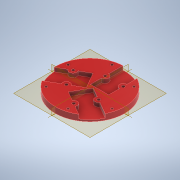
# Autodesk Inventor part: Base
Saved by Autodesk Inventor 2021 (Build 250183000, 183)
## iProperties
Created: 2026-04-21
Part Number: Base
Material: Generic
Document SubType Name: Modeling
Designer: Admin
Density: 1 g/cm^3
Appearance: Red
Author: Admin
Autodesk Inventor part; units mm, degrees
sketch "Sketch1" plane through (0, 0, 0) normal (0, 1, 0) x (-1, 0, 0)
  line L0 (-25, -40) -> (5, -40)
  line L1 (5, -40) -> (5, 0)
  line L2 (5, 0) -> (-25, 0)
  line L3 (-25, 0) -> (-25, -40)
  line L4 (-25, -40) -> (5, 0) construction
  line L5 (5, -40) -> (-25, 0) construction
  line L6 (-36.6337, 0) -> (44.8023, 0) projected
  line L7 (0, -54.5971) -> (0, 47.5827) projected
  point P0 (-10, -20)
  point P1 (0, -40)
  point P2 (0, 0)
  dimension "d15" = 30
  dimension "d16" = 40
  dimension "d17" = 10
  constraints: 12 end point, 2 midpoint, 2 parallel, 1 horizontal, 1 perpendicular, 1 point on line
  measures "d15" distance of L0.start L0.end
  measures "d16" distance of L2.end L0.start
  measures "d17" distance from line of L7 point (-10, -20)
extrude "Extrusion1" add sketch "Sketch1" along normal blind 8
pattern_circular "Circular Pattern2" count 3 over 360 about axis through (0, -10, 0) along (0, 1, 0) of "Extrusion1"
sketch "Sketch2" plane through (0, 8, 0) normal (0, 1, 0) x (1, 0, 0)
  line L0 (0, 54.5971) -> (0, -47.5827) projected
  line L1 (22.5, 40) -> (-2.5, 40)
  line L2 (-2.5, 40) -> (-2.5, 3)
  line L3 (-2.5, 3) -> (22.5, 3)
  line L4 (22.5, 3) -> (22.5, 40)
  line L5 (25, 40) -> (-5, 40) projected
  circle A0 centre (-2.5, 23) radius 5
  circle A1 centre (22.5, 23) radius 5
  point P0 (0, 0)
  point P1 (10, 40)
  point P2 (22.5, 18)
  point P3 (22.5, 28)
  point P4 (-2.5, 28)
  point P5 (-2.5, 18)
  dimension "d18" = 25
  dimension "d19" = 37
  dimension "d21" = 10
  dimension "d24" = 20
  dimension "d25" = 20
  constraints: 8 end point, 2 centre point, 2 midpoint, 2 parallel, 2 point on line, 1 equal radius, 1 horizontal, 1 perpendicular
  measures "d18" distance between parallel lines of L2 L4
  measures "d19" distance of L3.end L1.start
  measures "d21" diameter of A1
  measures "d24" distance from line of L3 A1.centre
  measures "d25" distance from line of L3 A0.centre
extrude "Extrusion2" cut sketch "Sketch2" against normal blind 5.5 contours L1 L4 A1 L3 L0 A0 | L0 A0 L2 L1 | L0 L3 L2 A0
pattern_circular "Circular Pattern3" count 3 over 360 about axis through (0, -10, 0) along (0, 1, 0) of "Extrusion2"
sketch "Sketch3" plane through (0, 0, 0) normal (0, 1, 0) x (-1, 0, 0)
  line L0 (12.5, -21.6506) -> (47.141, -1.6506) projected
  line L1 (32.141, 24.3301) -> (5, 8.6603) projected
  line L2 (12.5, 21.6506) -> (-22.141, 41.6506) projected
  line L3 (2.5, -40) -> (5, -40) projected
  line L4 (-35.891, 17.8349) -> (-37.141, 15.6699) projected
  line L5 (33.391, 22.1651) -> (32.141, 24.3301) projected
  line L6 (5, -8.6603) -> (12.5, -21.6506) projected
  line L7 (-23.391, 39.4856) -> (-12.9987, 33.4856) projected
  arc A0 (-12.9987, 33.4856) -> (-4.3385, 28.4856) centre (-8.6686, 30.9856) ccw projected
  line L8 (-4.3385, 28.4856) -> (8.6519, 20.9856) projected
  line L9 (8.6519, 20.9856) -> (-3.8481, -0.6651) projected
  line L10 (-3.8481, -0.6651) -> (-16.8385, 6.8349) projected
  arc A1 (-16.8385, 6.8349) -> (-25.4987, 11.8349) centre (-21.1686, 9.3349) ccw projected
  line L11 (-25.4987, 11.8349) -> (-35.891, 17.8349) projected
  line L12 (-35.891, 17.8349) -> (-37.141, 15.6699) projected
  line L13 (-37.141, 15.6699) -> (-10, 0) projected
  line L14 (-10, 0) -> (-25, 0) projected
  line L15 (-25, 0) -> (-25, -40) projected
  line L16 (-25, -40) -> (-22.5, -40) projected
  line L17 (-22.5, -40) -> (-22.5, -28) projected
  arc A2 (-22.5, -28) -> (-22.5, -18) centre (-22.5, -23) ccw projected
  line L18 (-22.5, -18) -> (-22.5, -3) projected
  line L19 (-22.5, -3) -> (2.5, -3) projected
  line L20 (2.5, -3) -> (2.5, -18) projected
  arc A3 (2.5, -18) -> (2.5, -28) centre (2.5, -23) ccw projected
  line L21 (2.5, -28) -> (2.5, -40) projected
  line L22 (2.5, -40) -> (5, -40) projected
  line L23 (5, -40) -> (5, -8.6603) projected
  line L24 (5, -8.6603) -> (12.5, -21.6506) projected
  line L25 (12.5, -21.6506) -> (47.141, -1.6506) projected
  line L26 (47.141, -1.6506) -> (45.891, 0.5144) projected
  line L27 (45.891, 0.5144) -> (35.4987, -5.4856) projected
  arc A4 (35.4987, -5.4856) -> (26.8385, -10.4856) centre (31.1686, -7.9856) ccw projected
  line L28 (26.8385, -10.4856) -> (13.8481, -17.9856) projected
  line L29 (13.8481, -17.9856) -> (1.3481, 3.6651) projected
  line L30 (1.3481, 3.6651) -> (14.3385, 11.1651) projected
  arc A5 (14.3385, 11.1651) -> (22.9987, 16.1651) centre (18.6686, 13.6651) ccw projected
  line L31 (22.9987, 16.1651) -> (33.391, 22.1651) projected
  line L32 (33.391, 22.1651) -> (32.141, 24.3301) projected
  line L33 (32.141, 24.3301) -> (5, 8.6603) projected
  line L34 (5, 8.6603) -> (12.5, 21.6506) projected
  line L35 (12.5, 21.6506) -> (-22.141, 41.6506) projected
  line L36 (-22.141, 41.6506) -> (-23.391, 39.4856) projected
  line L37 (-37.141, 15.6699) -> (-10, 0) projected
  line L38 (45.891, 0.5144) -> (48.967, 2.2903)
  line L39 (46.405, 29.6787) -> (33.391, 22.1651)
  line L40 (2.5, -40) -> (2.5, -52.4584)
  line L41 (-22.5, -40) -> (-22.5, -42.2166)
  line L42 (-35.891, 17.8349) -> (-42.369, 21.575)
  line L43 (-23.391, 39.4856) -> (-31.2964, 44.0497)
  line L44 (-25.4987, 11.8349) -> (-35.891, 17.8349) projected
  line L45 (-23.391, 39.4856) -> (-12.9987, 33.4856) projected
  line L46 (2.5, -28) -> (2.5, -40) projected
  line L47 (-22.5, -40) -> (-22.5, -28) projected
  line L48 (45.891, 0.5144) -> (35.4987, -5.4856) projected
  line L49 (22.9987, 16.1651) -> (33.391, 22.1651) projected
  circle A6 centre (0, 0) radius 47.5
  point P0 (5, -46.9042)
  point P1 (38.1202, 27.7822)
  point P2 (5, 8.6603)
  point P3 (39.8292, 25.8821)
  point P4 (-24.9784, 40.4021)
  point P5 (-42.3292, 21.552)
  point P6 (-22.5, -41.833)
  point P7 (2.5, -47.4342)
  point P8 (47.4784, 1.4309)
  dimension "d49" = 95
  constraints: 12 end point, 6 collinear, 1 centre point, 1 coincident, 1 point on line
  measures "d49" diameter of A6
extrude "Extrusion3" add sketch "Sketch3" along normal up to surface (8 mm away) contours L0 L26 L38 A6 L40 L3 L23 L6 | L39 L5 L1 L34 L2 L36 L43 A6 | A6 L42 L4 L13 L14 L15 L16 L41
sketch "Sketch8" plane through (0, 8, 0) normal (0, 1, 0) x (1, 0, 0)
  arc A0 (-2.5, 18) -> (-2.5, 28) centre (-2.5, 23) ccw projected
  arc A1 (-35.4987, 5.4856) -> (-26.8385, 10.4856) centre (-31.1686, 7.9856) ccw projected
  point P0 (0, 0)
  constraints: 2 coincident
hole "Hole1" at (-31.1686, 8, -7.9856) at (-2.5, 8, -23) direction (0, -1, 0) diameter 4 depth 26
pattern_circular "Circular Pattern4" count 3 over 360 about axis through (0, -10, 0) along (0, 1, 0) of "Hole1"
sketch "Sketch9" plane through (0, 0, 0) normal (0, 1, 0) x (-1, 0, 0)
  line L0 (-22.5, -41.833) -> (-22.5, -40) projected
  circle A0 centre (0, 0) radius 47.5
  circle A1 centre (-22.5, -23) radius 2 projected
  circle A2 centre (-21.1686, 9.3349) radius 2 projected
  circle A3 centre (-8.6686, 30.9856) radius 2 projected
  circle A4 centre (18.6686, 13.6651) radius 2 projected
  circle A5 centre (31.1686, -7.9856) radius 2 projected
  circle A6 centre (2.5, -23) radius 2 projected
  line L1 (-12.9987, 33.4856) -> (-24.9784, 40.4021) projected
  arc A7 (-12.9987, 33.4856) -> (-4.3385, 28.4856) centre (-8.6686, 30.9856) ccw projected
  line L2 (-4.3385, 28.4856) -> (8.6519, 20.9856) projected
  line L3 (8.6519, 20.9856) -> (-3.8481, -0.6651) projected
  line L4 (-3.8481, -0.6651) -> (-16.8385, 6.8349) projected
  arc A8 (-16.8385, 6.8349) -> (-25.4987, 11.8349) centre (-21.1686, 9.3349) ccw projected
  line L5 (-42.3292, 21.552) -> (-25.4987, 11.8349) projected
  arc A9 (-42.3292, 21.552) -> (-22.5, -41.833) centre (0, 0) ccw projected
  line L6 (-22.5, -41.833) -> (-22.5, -28) projected
  arc A10 (-22.5, -28) -> (-22.5, -18) centre (-22.5, -23) ccw projected
  line L7 (-22.5, -18) -> (-22.5, -3) projected
  line L8 (-22.5, -3) -> (2.5, -3) projected
  line L9 (2.5, -3) -> (2.5, -18) projected
  arc A11 (2.5, -18) -> (2.5, -28) centre (2.5, -23) ccw projected
  line L10 (2.5, -47.4342) -> (2.5, -28) projected
  arc A12 (2.5, -47.4342) -> (47.4784, 1.4309) centre (0, 0) ccw projected
  line L11 (35.4987, -5.4856) -> (47.4784, 1.4309) projected
  arc A13 (35.4987, -5.4856) -> (26.8385, -10.4856) centre (31.1686, -7.9856) ccw projected
  line L12 (26.8385, -10.4856) -> (13.8481, -17.9856) projected
  line L13 (13.8481, -17.9856) -> (1.3481, 3.6651) projected
  line L14 (1.3481, 3.6651) -> (14.3385, 11.1651) projected
  arc A14 (14.3385, 11.1651) -> (22.9987, 16.1651) centre (18.6686, 13.6651) ccw projected
  line L15 (39.8292, 25.8821) -> (22.9987, 16.1651) projected
  arc A15 (39.8292, 25.8821) -> (-24.9784, 40.4021) centre (0, 0) ccw projected
  line L16 (-22.5, -40) -> (-22.5, -28) projected
  line L17 (2.5, -40) -> (-22.5, -40) projected
  line L18 (2.5, -28) -> (2.5, -40) projected
  arc A16 (2.5, -18) -> (2.5, -28) centre (2.5, -23) ccw projected
  line L19 (2.5, -3) -> (2.5, -18) projected
  line L20 (-22.5, -3) -> (2.5, -3) projected
  line L21 (-22.5, -18) -> (-22.5, -3) projected
  arc A17 (-22.5, -28) -> (-22.5, -18) centre (-22.5, -23) ccw projected
  line L22 (45.891, 0.5144) -> (35.4987, -5.4856) projected
  line L23 (33.391, 22.1651) -> (45.891, 0.5144) projected
  line L24 (22.9987, 16.1651) -> (33.391, 22.1651) projected
  arc A18 (14.3385, 11.1651) -> (22.9987, 16.1651) centre (18.6686, 13.6651) ccw projected
  line L25 (1.3481, 3.6651) -> (14.3385, 11.1651) projected
  line L26 (13.8481, -17.9856) -> (1.3481, 3.6651) projected
  line L27 (26.8385, -10.4856) -> (13.8481, -17.9856) projected
  arc A19 (35.4987, -5.4856) -> (26.8385, -10.4856) centre (31.1686, -7.9856) ccw projected
  line L28 (-23.391, 39.4856) -> (-12.9987, 33.4856) projected
  line L29 (-35.891, 17.8349) -> (-23.391, 39.4856) projected
  line L30 (-25.4987, 11.8349) -> (-35.891, 17.8349) projected
  arc A20 (-16.8385, 6.8349) -> (-25.4987, 11.8349) centre (-21.1686, 9.3349) ccw projected
  line L31 (-3.8481, -0.6651) -> (-16.8385, 6.8349) projected
  line L32 (8.6519, 20.9856) -> (-3.8481, -0.6651) projected
  line L33 (-4.3385, 28.4856) -> (8.6519, 20.9856) projected
  arc A21 (-12.9987, 33.4856) -> (-4.3385, 28.4856) centre (-8.6686, 30.9856) ccw projected
  point P0 (47.4784, 1.4309)
  constraints: 1 coincident, 3 other
extrude "Extrusion6" add sketch "Sketch9" along normal up to surface (2.5 mm away) contours L0 L17 L10 A0 | A0 L1 L29 L5 | A0 L11 L23 L15
sketch "Sketch10" plane through (0, 0, 0) normal (0, -1, 0) x (1, 0, 0)
  circle A0 centre (8.6686, 30.9856) radius 2 projected
  circle A1 centre (21.1686, 9.3349) radius 2 projected
  line L0 (8.6686, 30.9856) -> (21.1686, 9.3349) construction
  circle A2 centre (22.5, -23) radius 2 projected
  circle A3 centre (-2.5, -23) radius 2 projected
  line L1 (22.5, -23) -> (-2.5, -23) construction
  circle A4 centre (-31.1686, -7.9856) radius 2 projected
  circle A5 centre (-18.6686, 13.6651) radius 2 projected
  line L2 (-31.1686, -7.9856) -> (-18.6686, 13.6651) construction
  point P0 (0, 0)
  point P1 (14.9186, 20.1603)
  point P2 (10, -23)
  point P3 (-24.9186, 2.8397)
  constraints: 6 end point, 3 midpoint, 1 horizontal
sketch "Sketch12" plane through (0, 8, 0) normal (0, 1, 0) x (1, 0, 0)
  circle A0 centre (0, 0) radius 42.5
  line L0 (-39.8292, -25.8821) -> (-22.9987, -16.1651) projected
  line L1 (12.9987, -33.4856) -> (24.9784, -40.4021) projected
  line L2 (-30.052, -30.052) -> (0, 0)
  line L3 (0, 0) -> (10.9998, -41.0518)
  line L4 (59.5, 0) -> (-59.5, 0) projected
  dimension "d60" = 85
  dimension "d66" = 45
  dimension "d67" = 75
  constraints: 4 end point, 2 coincident, 2 point on circle, 1 centre point
  measures "d60" diameter of A0
  measures "d66" angle of L4 L2
  measures "d67" angle of L4 L3
hole "Hole2" at (-30.052, 8, 30.052) at (10.9998, 8, 41.0518) direction (0, -1, 0) diameter 3.4 depth 80 clearance for "Countersunk Flat Head Screw ISO 2009/7046" size "M3" standard "ISO"
pattern_circular "Circular Pattern5" count 3 over 360 about axis through (0, -10, 0) along (0, 1, 0) of "Hole2"
sketch "Sketch13" plane through (0, 0, 0) normal (0, -1, 0) x (1, 0, 0)
  circle A0 centre (0, 0) radius 10.5 construction
  circle A1 centre (14.9178, -1.5679) radius 4.5
  line L0 (0, 0) -> (14.9178, -1.5679) construction
  line L1 (0, -66.5) -> (0, 66.5) construction
  line L2 (15.3882, 2.9074) -> (14.4475, -6.0433)
  dimension "d68" = 21
  dimension "d69" = 9
  dimension "d70" = 96
  constraints: 4 end point, 2 centre point, 2 point on circle, 1 coincident, 1 midpoint, 1 perpendicular, 1 tangent
  measures "d68" diameter of A0
  measures "d69" diameter of A1
  measures "d70" angle of L1 L0
extrude "Extrusion7" cut sketch "Sketch13" against normal blind 2 contours L2 A1 picked at (12.887, -2.2113)
equation "\"d25\" = d24"
body "Solid1"
